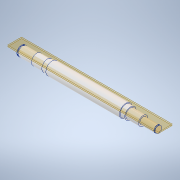
# Autodesk Inventor part: 1.2_3_Shaft_A
Saved by Autodesk Inventor 2021 (Build 250183000, 183)
## iProperties
Created: 2025-11-13
Part Number: 1.2_3_Shaft_A
Material: Aluminum 6061
Document SubType Name: Modeling
Designer: Admin
Density: 2.7 g/cm^3
Appearance: Aluminum - Flat
Mass: 124.801 g
Surface Area: 113.837 cm^2
Volume: 46.2227 cm^3
Author: Admin
Autodesk Inventor part; units mm, degrees
ref_plane "YZ Plane" through (0, 0, 0) normal (1, 0, 0) x (0, 1, 0)
ref_plane "XY Plane" through (0, 0, 0) normal (0, 0, 1) x (1, 0, 0)
sketch "Sketch1" plane through (0, 0, 0) normal (0, 1, 0) x (-1, 0, 0)
  line L0 (4.7929, 0) -> (-12.4616, 0) construction
  line L1 (-12.4616, 0) -> (-12.4616, -0.4793) construction
  line L2 (-12.4616, -0.4793) -> (4.7929, -0.4793) construction
  line L3 (4.7929, -0.4793) -> (4.7929, 0) construction
  line L4 (141.94, 0) -> (-144.64, 0) projected
  line L5 (0, -11.4) -> (0, 1.9) projected
  line L6 (101, 0) -> (101, -7)
  line L7 (101, -7) -> (100.1, -7)
  line L8 (100.1, -7) -> (100.1, -6.7)
  line L9 (100.1, -6.7) -> (99, -6.7)
  line L10 (99, -6.7) -> (99, -7)
  line L11 (99, -7) -> (78, -7)
  line L12 (55, -8.5) -> (55, -9.5)
  line L13 (55, -9.5) -> (-55, -9.5)
  line L14 (-55, -9.5) -> (-55, -8.5)
  line L15 (-81, -5) -> (-102, -5)
  line L16 (-102, -5) -> (-102, -4.8)
  line L17 (-102, -4.8) -> (-103.1, -4.8)
  line L18 (-103.1, -4.8) -> (-103.1, -5)
  line L19 (-103.1, -5) -> (-103.7, -5)
  line L20 (-103.7, -5) -> (-103.7, 0)
  line L21 (-81, -5) -> (-81, -7)
  line L22 (-81, -7) -> (-62, -7)
  line L23 (-62, -7) -> (-62, -8.5)
  line L24 (-62, -8.5) -> (-55, -8.5)
  line L25 (55, -8.5) -> (62, -8.5)
  line L26 (62, -8.5) -> (62, -8)
  line L27 (62, -8) -> (78, -8)
  line L28 (78, -8) -> (78, -7)
  point P0 (0, 0)
  point P1 (0, -9.5)
  dimension "d4" = 1.1
  dimension "d5" = 1.1
  dimension "d6" = 0.6
  dimension "d7" = 0.9
  dimension "d8" = 7
  dimension "d9" = 5
  dimension "d11" = 0.2
  dimension "d12" = 21
  dimension "d16" = 110
  dimension "d19" = 26
  dimension "d20" = 7
  dimension "d21" = 21
  dimension "d22" = 2
  dimension "d25" = 7
  dimension "d26" = 23
  dimension "d29" = 9.5
  dimension "d30" = 1
  dimension "d31" = 8.5
  dimension "d37" = 6.7
  constraints: 54 end point, 18 perpendicular, 7 point on line, 2 collinear, 2 horizontal, 2 vertical, 1 midpoint, 1 parallel
  measures "d4" distance of L8.end L9.end
  measures "d5" distance of L16.end L17.end
  measures "d6" distance of L18.end L19.end
  measures "d7" distance of L6.end L7.end
  measures "d8" distance of L6.start L6.end
  measures "d9" distance of L19.end L20.end
  measures "d11" distance of L17.end L18.end
  measures "d12" distance of L10.end L11.end
  measures "d16" distance between parallel lines of L14 L12
  measures "d19" distance between parallel lines of L14 L21
  measures "d20" distance of L23.end L14.end
  measures "d21" distance between parallel lines of L21 L16
  measures "d22" distance of L15.start L21.end
  measures "d25" distance of L12.start L25.end
  measures "d26" distance between parallel lines of L28 L12
  measures "d29" distance between parallel lines of L4 L13
  measures "d30" distance between parallel lines of L11 L27
  measures "d31" distance between parallel lines of L4 L24
  measures "d37" distance between parallel lines of L4 L9
revolve "Revolution1" add sketch "Sketch1" angle 360 about axis through (-10, 0, 0) along (1, 0, 0)
ref_plane "Work Plane1" through (-88.5, 7, 0) normal (0, 1, 0) x (-1, 0, 0)
sketch "Sketch2" plane through (-88.5, 7, 0) normal (0, 1, 0) x (-1, 0, 0)
  line L0 (5, 0) -> (-6, 0) construction
  line L1 (5, 2.5) -> (-6, 2.5)
  line L2 (-6, -2.5) -> (5, -2.5)
  arc A0 (5, -2.5) -> (5, 2.5) centre (5, 0) ccw
  arc A1 (-6, 2.5) -> (-6, -2.5) centre (-6, 0) ccw
  line L3 (53.44, 0) -> (-233.14, 0) projected
  line L4 (-10.5, 8) -> (-10.5, -8) projected
  point P0 (-88.5, 0)
  point P1 (-0.5, 0)
  dimension "d32" = 5
  dimension "d33" = 11
  dimension "d34" = 10
  constraints: 8 end point, 4 point on circle, 4 tangent, 2 centre point, 1 horizontal, 1 midpoint, 1 parallel, 1 point on line
  measures "d32" distance between parallel lines of L1 L2
  measures "d33" distance of L0.start L0.end
  measures "d34" distance from line of L4 point (-0.5, 0)
extrude "Extrusion1" [suppressed]
ref_plane "Work Plane2" through (91.5, 5, 0) normal (0, 1, 0) x (-1, 0, 0)
sketch "Sketch4" plane through (91.5, 5, 0) normal (0, 1, 0) x (-1, 0, 0)
  line L0 (-3.5, 0) -> (3.5, 0) construction
  line L1 (-3.5, -1.5) -> (3.5, -1.5)
  line L2 (3.5, 1.5) -> (-3.5, 1.5)
  arc A0 (-3.5, 1.5) -> (-3.5, -1.5) centre (-3.5, 0) ccw
  arc A1 (3.5, -1.5) -> (3.5, 1.5) centre (3.5, 0) ccw
  line L3 (-10.5, 5) -> (-10.5, -5) projected
  point P0 (91.5, 0)
  point P1 (0, 0)
  dimension "d45" = 3
  dimension "d46" = 7
  dimension "d47" = 10.5
  constraints: 8 end point, 4 point on circle, 4 tangent, 2 centre point, 1 horizontal, 1 midpoint, 1 parallel, 1 point on line
  measures "d45" distance between parallel lines of L1 L2
  measures "d46" distance of L0.start L0.end
  measures "d47" distance from line of point (0, 0) L3
extrude "Extrusion3" [suppressed]
body "Solid1"
